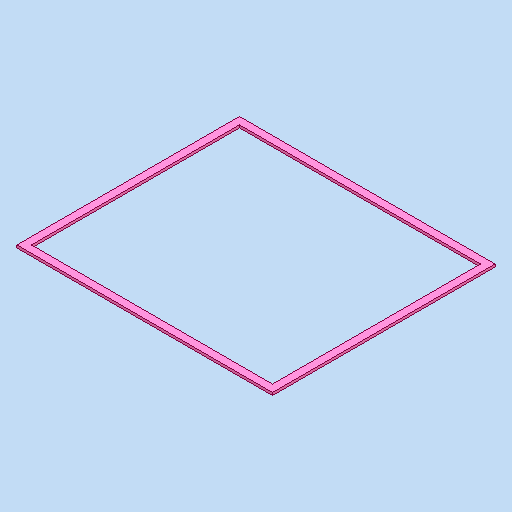
# Autodesk Inventor part: MM0861AN105_G11_303
Saved by Autodesk Inventor 2023.3 (Build 273359000, 359)
## iProperties
Part Number: MM0861AN105_G11_303
Material: Generisch
Description: =<RBPARTNOTITLE2>
Document SubType Name: Modeling
Designer: ric7an
Mass: 61.776 g
Surface Area: 421.2 cm^2
Volume: 61.776 cm^3
Density: 1 g/cm^3
Appearance: pink AnP
Vendor: Haewa
RBDOCUMENTTYPE: DRF
RBDOCUMENTVERSION: 00
RBDRAWINGMAINSCALE: 1:1
RBDRAWINGMISSINGSPEC: --
RBDRAWINGVOLUME: --
RBGBEDGESIN1: +0,5
RBGBEDGESIN2: +0,2
RBGBEDGESOUT1: -0,3
RBGBEDGESOUT2: -0,1
RBMATERIAL: --
RBMATMEETS: --
RBMATNO: =<Part Number>
RBPARTMADEOF: 3080-0102-18-00 / 1,5 m
RBPARTNO: SIEHE MNR
RBPARTNOTITLE1: gasket
RBPARTNOTITLE2: Dichtungsgummi selbstklebend
RBPARTSAFETYINDICATOR: --
RBSURFACE: --
RBSURFACE2: --
RBZEDGESNORM: ISO13715:2002-06
RBZGENDIMCLASS: m
RBZGENDIMNORM: ISO 2768-1:1989-11
RBZGENGEOCLASS: H
RBZGENGEONORM: ISO 2768-2:1989-11
RBZSURFACENORM: ISO13D2:2002-02
RBZTOLERANCENORM: ISO 14405-1:2010-12
AnP_Material: =<Material>
AnP_TemplVers: 20190222
AnP_Kategorie: 2
Author: ric7an
Keywords: =<RBPARTMADEOF>
Comments: =<RBSURFACE2>
Revision Number: 01
Autodesk Inventor part; units mm, degrees
ref_plane "YZ Plane" through (0, 0, 0) normal (1, 0, 0) x (0, 1, 0)
ref_plane "XZ Plane" through (0, 0, 0) normal (0, 1, 0) x (-1, 0, 0)
ref_plane "XY Plane" through (0, 0, 0) normal (0, 0, 1) x (1, 0, 0)
sketch "Skizze1" plane through (0, 0, 0) normal (0, 0, 1) x (1, 0, 0)
  line L0 (-182.5, 157.5) -> (182.5, 157.5)
  line L1 (182.5, 157.5) -> (182.5, -157.5)
  line L2 (182.5, -157.5) -> (-182.5, -157.5)
  line L3 (-182.5, -157.5) -> (-182.5, 157.5)
  line L4 (-193.5, 168.5) -> (193.5, 168.5)
  line L5 (193.5, 168.5) -> (193.5, -168.5)
  line L6 (193.5, -168.5) -> (-193.5, -168.5)
  line L7 (-193.5, -168.5) -> (-193.5, 168.5)
  line L8 (0, 235.9) -> (0, -235.9) projected
  line L9 (-270.9, 0) -> (270.9, 0) projected
  point P0 (0, 0)
  dimension "d0" = 11
  dimension "d1" = 11
  dimension "d6" = 315
  dimension "d7" = 365
  constraints: 16 end point, 4 parallel, 2 horizontal, 2 perpendicular, 4 other
  measures "d0" distance between parallel lines of L4 L0
  measures "d1" distance between parallel lines of L7 L3
  measures "d6" distance between parallel lines of L2 L0
  measures "d7" distance of L0.start L0.end
extrude "Extrusion1" add sketch "Skizze1" along normal blind 4 contours L3 L9 L7 L4 L8 L0 | L8 L4 L5 L9 L1 L0 | L3 L2 L8 L6 L7 L9 | L9 L5 L6 L8 L2 L1
equation "\"d1\" = d0"
